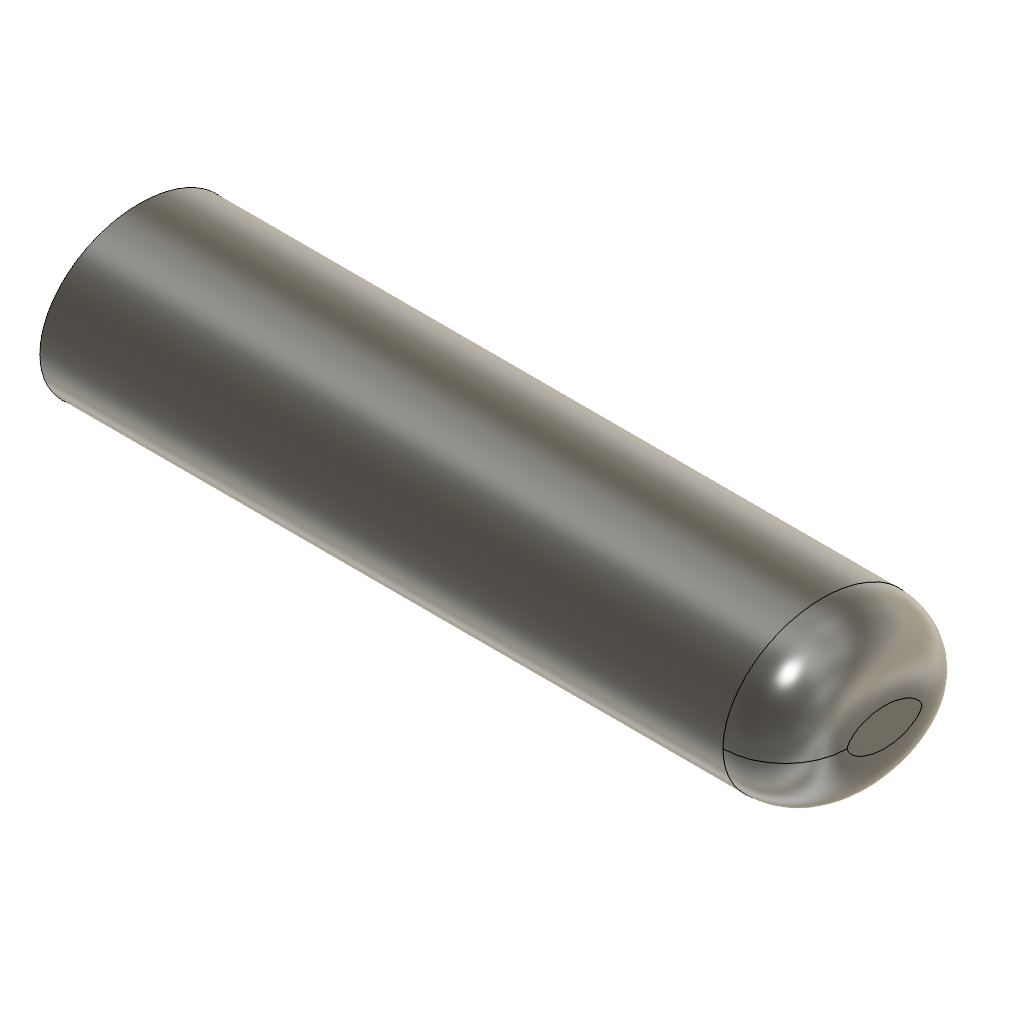
finger_v1 (Autodesk Fusion 360 design; units mm, degrees)
part number: 2026-10-19-20-18-20-436
Autodesk Fusion 360 part; units mm, degrees
sketch "Esquisse2" plane through (0, 0, 0) normal (1, 0, 0) x (0, 1, 0)
  ellipse E0 centre (0, 0) end of major axis (8, 0) minor radius 6.5
  line L0 (-8, 0) -> (8, 0) construction
  line L1 (0, -6.5) -> (0, 6.5) construction
  dimension "d7" = 16
  dimension "d8" = 13
  constraint coincident E0 L0.start
  constraint coincident E0 L0.end
  constraint coincident E0 L1.start
  constraint coincident E0 L1.end
  constraint coincident E0.centre origin
  constraint horizontal L0
  measures "d7" distance of E0
extrude "Extrusion1" add sketch "Esquisse2" along normal blind 60
fillet "Congé1" radius 5 1 faces at (60, -0.0579, -2.16)
sketch "Esquisse3" plane through (0, 0, 0) normal (-1, 0, 0) x (0, -1, 0)
  ellipse E0 centre (0, 0) end of major axis (-8, 0) minor radius 6.5
  circle A0 centre (0, 0) radius 1
  dimension "d15" = 2
  constraint coincident E0.centre A0.centre
  measures "d15" diameter of A0
extrude "Extrusion2" cut sketch "Esquisse3" against normal blind 52 contours A0
equation "doigt_largeur = 16 mm" comment "largeur du doigt au niveau de l'ongle"
equation "doigt_epaisseur = 13 mm" comment "épaisseur ongle → pulpe"
equation "doigt_longueur = 60 mm" comment "longueur totale (la pince couvre ~25-30 mm)"
equation "vaisseau_diam = 2 mm" comment "diamètre du canal pour le liquide"
equation "vaisseau_decalage = 0 mm" comment "décalage du canal par rapport au centre"
equation "d7 = doigt_largeur"
equation "d8 = doigt_epaisseur"
equation "d9 = doigt_longueur"
equation "bout_rayon = 5 mm"
equation "d13 = bout_rayon"
equation "vaisseau_fond = 8 mm"
equation "d15 = vaisseau_diam"
equation "d16 = -doigt_longueur + vaisseau_fond"
named bodies: "doigt"
